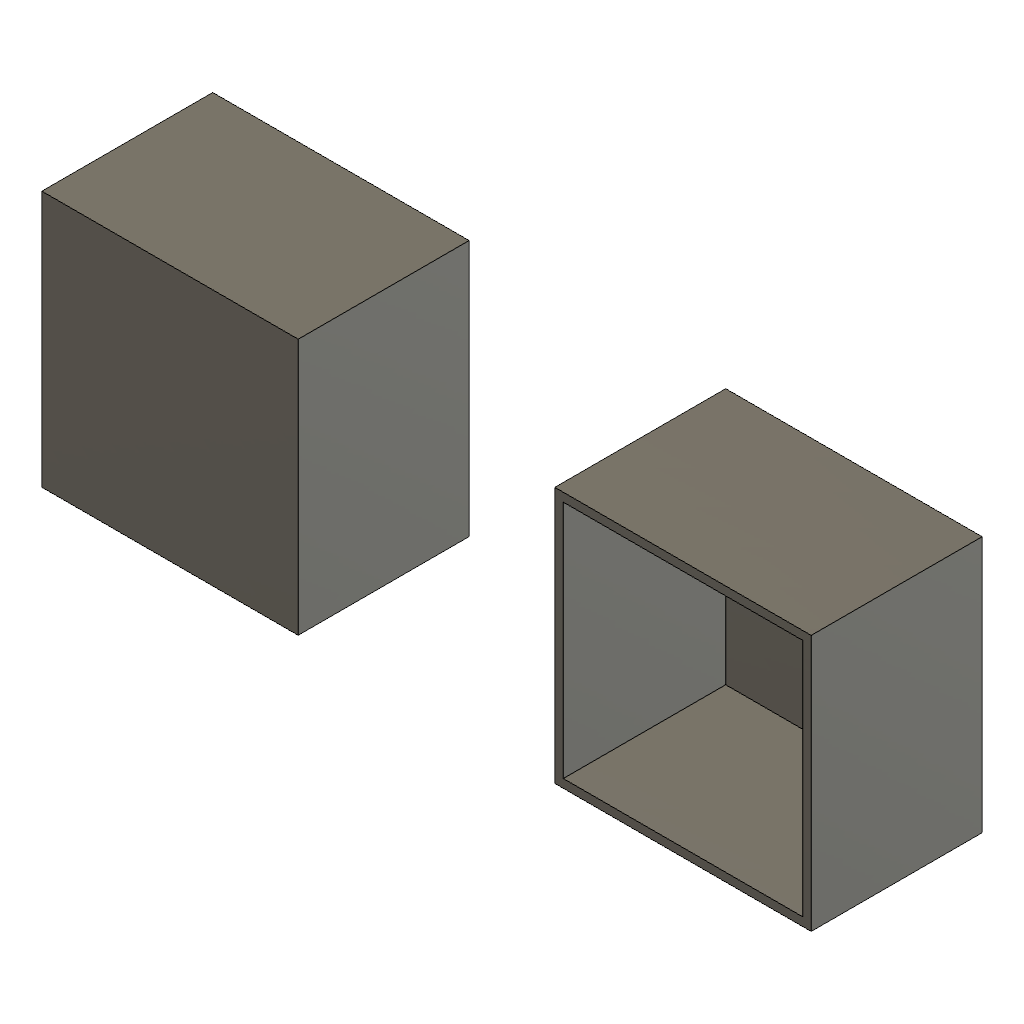
shell_body_and_other_face (Autodesk Fusion 360 design; units mm, degrees)
part number: 2026-10-20-23-40-30-433
Autodesk Fusion 360 part; units mm, degrees
sketch "InputSourceSketch1" plane through (0, 0, 0) normal (0, 0, 1) x (1, 0, 0)
  line L0 (10, 10) -> (40, 10)
  line L1 (40, 10) -> (40, 40)
  line L2 (40, 40) -> (10, 40)
  line L3 (10, 40) -> (10, 10)
extrude "InputSourceExtrude1" add sketch "InputSourceSketch1" along normal blind 20 makes body 1
sketch "InputSourceSketch2" plane through (0, 0, 0) normal (0, 0, 1) x (1, 0, 0)
  line L0 (70, 10) -> (100, 10)
  line L1 (100, 10) -> (100, 40)
  line L2 (100, 40) -> (70, 40)
  line L3 (70, 40) -> (70, 10)
extrude "InputSourceExtrude2" add sketch "InputSourceSketch2" along normal blind 20 separate body makes body 2
shell "ProbeScaleShellInput" thickness 1 removed faces 1 at (80, 30, 20) bodies 1 on bodies 2
named bodies: "InputBody1", "InputBody2"
